MOD-GRID Baseplate 12x8 (Autodesk Fusion 360 design; units mm, degrees)
part number: 2026-10-23-12-37-37-115
Autodesk Fusion 360 part; units mm, degrees
sketch "Plate outline" plane through (0, 0, 0) normal (0, 0, 1) x (1, 0, 0)
  line L0 (0, 0) -> (99, 0)
  line L1 (99, 0) -> (99, 67)
  line L2 (99, 67) -> (0, 67)
  line L3 (0, 67) -> (0, 0)
  dimension "d102" = 99
  dimension "d103" = 67
  constraint coincident L0.start L3.end
  measures "d102" horizontal distance of L0.start L0.end
  measures "d103" vertical distance of L0.end L1.end
extrude "Extrude10" add sketch "Plate outline" along normal blind 3
fillet "Fillet5" radius 3 4 edges at (0, 67, 1.5) (99, 67, 1.5) (99, 0, 1.5) (0, 0, 1.5)
sketch "Hole cell" plane through (0, 0, 0) normal (0, 0, 1) x (1, 0, 0)
  line L0 (3, 3) -> (8.14, 3)
  line L1 (8.14, 3) -> (8.14, 8.14)
  line L2 (8.14, 8.14) -> (3, 8.14)
  line L3 (3, 8.14) -> (3, 3)
  dimension "d108" = 3
  dimension "d109" = 3
  dimension "d110" = 5.14
  dimension "d111" = 5.14
  measures "d108" horizontal distance of origin L0.start
  measures "d109" vertical distance of origin L0.start
  measures "d110" horizontal distance of L0.start L0.end
  measures "d111" vertical distance of L0.end L1.end
extrude "Extrude11" cut sketch "Hole cell" along normal blind 3 and the other way blind 3
chamfer "Chamfer9" distance 0.3 angle 45 4 edges at (5.57, 3, 0) (8.14, 5.57, 0) (5.57, 8.14, 0) (3, 5.57, 0) tangent chain off
chamfer "Chamfer10" distance 0.4 angle 45 4 edges at (3, 5.57, 3) (5.57, 8.14, 3) (5.57, 3, 3) (8.14, 5.57, 3) tangent chain off
pattern_linear "R-Pattern5" count 12 spacing 8 along (1, 0, 0) count 8 spacing 8 along (0, 1, 0) of "Extrude11", "Chamfer9", "Chamfer10"
chamfer "Chamfer11" distance 0.3 angle 45 8 edges at (0.8787, 0.8787, 0) (49.5, 0, 0) (98.1213, 0.8787, 0) (99, 33.5, 0) (98.1213, 66.1213, 0) (49.5, 67, 0) (0.8787, 66.1213, 0) (0, 33.5, 0) tangent chain off
equation "grid_x = 12" comment "Cells along X - the main variable"
equation "grid_y = 8" comment "Cells along Y - the main variable"
equation "grid_pitch = 8 mm" comment "MOD-GRID pitch (measured from the official 4x12)"
equation "hole_size = 5 mm" comment "Square hole across flats (measured: 5.000)"
equation "hole_clear = 0.07 mm" comment "Per-side hole adjustment; raise if the connector is tight"
equation "plate_t = 3 mm" comment "Plate thickness (measured: 3.000)"
equation "border = 3 mm" comment "Edge to first hole; equals the wall between holes"
equation "corner_r = 3 mm" comment "Outer corner radius"
equation "first_layer_cham = 0.3 mm" comment "Elephant-foot chamfer on every bed-face edge"
equation "mouse_ear_r = 8 mm" comment "Mouse ear radius (ABS warp relief)"
equation "mouse_ear_t = 0.4 mm" comment "Mouse ear thickness (2 layers at 0.2 mm)"
equation "hole_w = hole_size + 2 * hole_clear" comment "Actual modelled hole width"
equation "plate_x = grid_pitch * grid_x + border" comment "Plate length (8n + 3)"
equation "plate_y = grid_pitch * grid_y + border" comment "Plate width (8n + 3)"
equation "ear_off = ( corner_r + 2 mm ) / sqrt(2) - corner_r" comment "Mouse ear centre, outside the corner arc"
equation "hole_lead_in = 0.4 mm" comment "Lead-in chamfer on the TOP of each hole so a peg starts square instead of jamming on a sharp lip. The official plate has none; this eases ENTRY but does not widen the parallel section, so it is NOT a fix for holes printing undersize - use hole_clear for that."
equation "d102 = plate_x"
equation "d103 = plate_y"
equation "d104 = plate_t"
equation "d107 = corner_r"
equation "d108 = border"
equation "d109 = border"
equation "d110 = hole_w"
equation "d111 = hole_w"
equation "d112 = plate_t"
equation "d114 = plate_t"
equation "d116 = first_layer_cham"
equation "d117 = hole_lead_in"
equation "d118 = grid_x"
equation "d119 = grid_y"
equation "d120 = grid_pitch"
equation "d121 = grid_pitch"
equation "d122 = first_layer_cham"
named bodies: "Baseplate"
